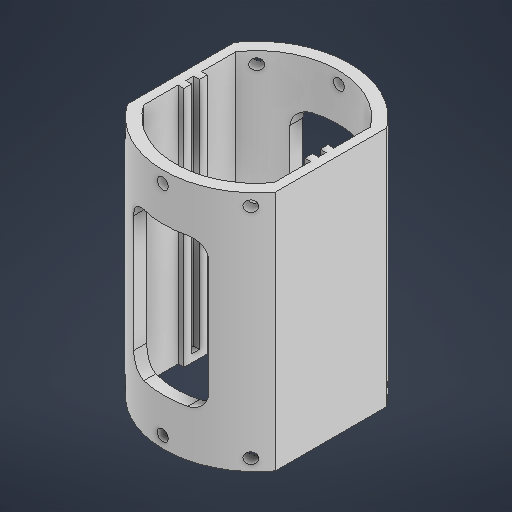
# Autodesk Inventor part: Avionics Holder
Saved by Autodesk Inventor 2027 (Build 310192060, 192F)
## iProperties
Created: 2026-07-27
Part Number: Avionics Holder
Material: PET Plastic
Document SubType Name: Modeling
Designer: troop
Density: 1.541 g/cm^3
Appearance: Default
Mass: 81.5144 g
Surface Area: 339.423 cm^2
Volume: 52.8971 cm^3
Author: troop
Autodesk Inventor part; units mm, degrees
sketch "Sketch1" plane through (0, 0, 0) normal (0, 1, 0) x (-1, 0, 0)
  line L0 (27.2914, 18.7675) -> (27.2914, -18.7675)
  line L1 (-26.6836, 19.6221) -> (-26.6836, -19.6221)
  arc A0 (27.2914, 18.7675) -> (-26.6836, 19.6221) centre (0, 0) ccw
  arc A1 (-26.6836, -19.6221) -> (27.2914, -18.7675) centre (0, 0) ccw
  line L2 (30.8982, 21.8545) -> (30.8982, -21.8545)
  line L3 (-30.3018, 22.6743) -> (-30.3018, -22.6743)
  arc A2 (30.8982, 21.8545) -> (-30.3018, 22.6743) centre (0, 0) ccw
  arc A3 (-30.3018, -22.6743) -> (30.8982, -21.8545) centre (0, 0) ccw
  line L4 (27.2914, -4.7625) -> (24.9102, -4.7625)
  line L5 (24.9102, -4.7625) -> (24.9102, -1.5875)
  line L6 (24.9102, -1.5875) -> (27.2914, -1.5875)
  line L7 (27.2914, -1.5875) -> (27.2914, -4.7625)
  line L8 (27.2914, 1.5875) -> (24.9102, 1.5875)
  line L9 (24.9102, 1.5875) -> (24.9102, 4.7625)
  line L10 (24.9102, 4.7625) -> (27.2914, 4.7625)
  line L11 (27.2914, 4.7625) -> (27.2914, 1.5875)
  line L12 (-26.6836, -4.7625) -> (-24.3023, -4.7625)
  line L13 (-24.3023, -4.7625) -> (-24.3023, -1.5875)
  line L14 (-24.3023, -1.5875) -> (-26.6836, -1.5875)
  line L15 (-26.6836, -1.5875) -> (-26.6836, -4.7625)
  line L16 (-26.6836, 1.5875) -> (-24.3023, 1.5875)
  line L17 (-24.3023, 1.5875) -> (-24.3023, 4.7625)
  line L18 (-24.3023, 4.7625) -> (-26.6836, 4.7625)
  line L19 (-26.6836, 4.7625) -> (-26.6836, 1.5875)
  point P0 (0.5069, 37.8426)
  point P1 (-25.4929, 1.5875)
  point P2 (27.2914, 4.7625)
  point P3 (27.2914, -1.5875)
  dimension "d5" = 61.2
  dimension "d6" = 43.709
  dimension "d7" = 30.8982
  dimension "d10" = 37.8426
  dimension "d11" = 21.8545
  dimension "d12" = 37.846
  dimension "d13" = 3.175
  dimension "d14" = 3.175
  dimension "d15" = 2.3813
  dimension "d16" = 2.3813
  dimension "d17" = 3.175
  dimension "d18" = 3.175
  dimension "d20" = 1.5875
  dimension "d21" = 1.5875
  dimension "d22" = 3.175
  dimension "d23" = 3.175
  dimension "d42" = 53.975
  dimension "d43" = 33.1216
  dimension "d44" = 33.1216
  dimension "d45" = 3.6068
  constraints: 40 end point, 10 parallel, 9 point on circle, 6 point on line, 4 centre point, 4 horizontal, 4 perpendicular, 2 vertical, 1 coincident, 1 midpoint
  measures "d5" distance between parallel lines of L3 L2
  measures "d6" distance of L2.start L2.end
  measures "d7" distance from line of L2 point (0, 0)
  measures "d10" vertical distance of point (0.507, 37.843) point (0, 0)
  measures "d11" vertical distance of A2.centre L2.start
  measures "d12" radius of A2
  measures "d13" distance between parallel lines of L8 L6
  measures "d14" distance from line of point (-25.493, 1.588) L14
  measures "d15" distance of L17.end L18.end
  measures "d16" distance of L9.end L10.end
  measures "d17" distance of L16.end L17.end
  measures "d18" distance of L12.end L13.end
  measures "d20" distance from line of A2.centre L14
  measures "d21" distance from line of point (0, 0) L6
  measures "d22" distance of L8.end L9.end
  measures "d23" distance of L4.end L5.end
  measures "d42" distance between parallel lines of L1 L0
  measures "d43" radius of A0
  measures "d44" radius of A1
  measures "d45" distance between parallel lines of L2 L0
extrude "Extrusion1" add sketch "Sketch1" along normal blind 98.425 contours L0 L8 L9 L10 | L18 L17 L16 L1 | L0 L4 L5 L6 | L14 L13 L12 L1 | L2 A3 L3 A2
ref_plane "Work Plane1" through (-0.5069, 98.425, 37.8426) normal (-0.0134, 0, 0.9999) x (0.9999, 0, 0.0134)
sketch "Sketch3" plane through (0, 0, 0) normal (0, -1, 0) x (1, 0, 0)
  line L0 (26.6836, 1.5875) -> (24.3023, 1.5875) projected
  line L1 (26.6836, 1.5875) -> (24.3023, 1.5875)
  line L2 (24.3023, 1.5875) -> (24.3023, -1.5875)
  line L3 (24.3023, -1.5875) -> (26.6836, -1.5875)
  line L4 (26.6836, -1.5875) -> (26.6836, 1.5875)
  line L5 (-27.2914, 1.5875) -> (-27.2914, -1.5875) projected
  line L6 (-27.2914, -1.5875) -> (-24.9102, -1.5875)
  line L7 (-24.9102, -1.5875) -> (-24.9102, 1.5875)
  line L8 (-24.9102, 1.5875) -> (-27.2914, 1.5875)
  line L9 (-27.2914, 1.5875) -> (-27.2914, -1.5875)
  point P0 (0, 0)
  point P1 (-28.7045, 1.5875)
  dimension "d32" = 2.3813
  constraints: 16 end point, 4 parallel, 2 horizontal, 2 perpendicular, 1 point on line
  measures "d32" distance of L5.end L6.end
extrude "Extrusion3" add sketch "Sketch3" against normal blind 3.175
ref_plane "Work Plane2" through (-0.5069, 98.425, 37.8426) normal (-0.0134, 0, 0.9999) x (0.9999, 0, 0.0134)
sketch "Sketch4" plane through (-0.5069, 98.425, 37.8426) normal (-0.0134, 0, 0.9999) x (0.9999, 0, 0.0134)
  circle A0 centre (0, -4.7625) radius 2.25
  line L0 (30.6027, 0) -> (-30.6027, 0) projected
  circle A1 centre (0, -93.6625) radius 2.25
  line L1 (30.6027, -98.425) -> (-30.6027, -98.425) projected
  point P0 (0, -98.425)
  point P1 (0, 0)
  point P2 (0, -98.425)
  dimension "d35" = 4.5
  dimension "d36" = 4.7625
  dimension "d37" = 0
  dimension "d46" = 4.5
  dimension "d47" = 0
  dimension "d48" = 4.7625
  constraints: 2 centre point, 2 midpoint
  measures "d35" diameter of A0
  measures "d36" distance from line of L0 A0.centre
  measures "d37" horizontal distance of point (0, 0) A0.centre
  measures "d46" diameter of A1
  measures "d47" horizontal distance of point (0, -98.425) A1.centre
  measures "d48" distance of point (0, -98.425) A1.centre
extrude "Extrusion4" cut sketch "Sketch4" against normal blind 76.2
ref_plane "Work Plane3" through (20.0422, 0, 32.1034) normal (0.5296, 0, 0.8483) x (0, 1, 0)
sketch "Sketch5" plane through (20.0422, 0, 32.1034) normal (0.5296, 0, 0.8483) x (0, 1, 0)
  circle A0 centre (4.7625, -6.8481) radius 2.25
  circle A1 centre (93.6625, -6.8481) radius 2.25
  line L0 (88.9, 0) -> (88.9, 34.7302) projected
  line L1 (0, -13.6963) -> (98.425, -13.6963) projected
  point P0 (0, 0)
  dimension "d49" = 4.5
  dimension "d52" = 4.5
  dimension "d54" = 4.7625
  dimension "d57" = 6.8481
  dimension "d60" = 6.8481
  dimension "d61" = 4.7625
  constraints: 2 centre point
  measures "d49" diameter of A0
  measures "d52" diameter of A1
  measures "d54" distance from line of L0 A1.centre
  measures "d57" distance from line of L1 A1.centre
  measures "d60" vertical distance of A0.centre point (0, 0)
  measures "d61" horizontal distance of point (0, 0) A0.centre
extrude "Extrusion5" cut sketch "Sketch5" against normal blind 25.4
ref_plane "Work Plane4" through (-21.4969, 0, 31.1481) normal (-0.568, 0, 0.823) x (0, -1, 0)
sketch "Sketch6" plane through (-21.4969, 0, 31.1481) normal (-0.568, 0, 0.823) x (0, -1, 0)
  circle A0 centre (-4.7625, -6.8481) radius 2.25
  circle A1 centre (-93.6625, -6.8481) radius 2.25
  line L0 (-98.425, 37.8182) -> (-98.425, -13.0164) projected
  point P0 (0, 0)
  dimension "d62" = 4.5
  dimension "d63" = 6.8481
  dimension "d64" = 4.7625
  dimension "d65" = 4.5
  dimension "d66" = 6.8481
  dimension "d67" = 4.7625
  constraints: 2 centre point
  measures "d62" diameter of A0
  measures "d63" vertical distance of point (0, 0) A0.centre
  measures "d64" horizontal distance of point (0, 0) A0.centre
  measures "d65" diameter of A1
  measures "d66" vertical distance of point (0, 0) A1.centre
  measures "d67" distance from line of L0 A1.centre
extrude "Extrusion6" cut sketch "Sketch6" against normal blind 25.4
ref_plane "Work Plane5" through (20.8949, 0, -31.5551) normal (0.5521, 0, -0.8338) x (0, 1, 0)
sketch "Sketch7" plane through (20.8949, 0, -31.5551) normal (0.5521, 0, -0.8338) x (0, 1, 0)
  circle A0 centre (4.7625, 6.8481) radius 2.25
  circle A1 centre (93.6625, 5.8982) radius 2.25
  line L0 (0, 12.7464) -> (98.425, 12.7464) projected
  line L1 (98.425, -37.8281) -> (98.425, 12.7464) projected
  point P0 (0, 0)
  dimension "d70" = 4.5
  dimension "d71" = 6.8481
  dimension "d72" = 4.7625
  dimension "d73" = 4.5
  dimension "d74" = 6.8481
  dimension "d75" = 4.7625
  constraints: 2 centre point
  measures "d70" diameter of A0
  measures "d71" vertical distance of point (0, 0) A0.centre
  measures "d72" horizontal distance of point (0, 0) A0.centre
  measures "d73" diameter of A1
  measures "d74" distance from line of L0 A1.centre
  measures "d75" distance from line of L1 A1.centre
extrude "Extrusion7" cut sketch "Sketch7" against normal blind 25.4
ref_plane "Work Plane6" through (-20.6549, 0, -31.7127) normal (-0.5458, 0, -0.8379) x (0, -1, 0)
sketch "Sketch8" plane through (-20.6549, 0, -31.7127) normal (-0.5458, 0, -0.8379) x (0, -1, 0)
  circle A0 centre (-4.7625, 6.8481) radius 2.25
  circle A1 centre (-93.6625, 6.8481) radius 2.25
  line L0 (-88.9, 0) -> (-9.525, 0) projected
  point P0 (0, 0)
  dimension "d78" = 4.5
  dimension "d79" = 4.5
  dimension "d80" = 6.8481
  dimension "d81" = 6.8481
  dimension "d82" = 4.7625
  dimension "d83" = 4.7625
  constraints: 2 centre point
  measures "d78" diameter of A0
  measures "d79" diameter of A1
  measures "d80" distance from line of L0 A1.centre
  measures "d81" vertical distance of point (0, 0) A0.centre
  measures "d82" horizontal distance of point (0, 0) A0.centre
  measures "d83" horizontal distance of L0.start A1.centre
extrude "Extrusion8" cut sketch "Sketch8" against normal blind 25.4
sketch "Sketch10" plane through (0, 0, 0) normal (0, 0, 1) x (1, 0, 0)
  line L0 (-15.6582, 79.375) -> (15.0618, 79.375)
  line L1 (15.0618, 79.375) -> (15.0618, 19.05)
  line L2 (15.0618, 19.05) -> (-15.6582, 19.05)
  line L3 (-15.6582, 19.05) -> (-15.6582, 79.375)
  line L4 (30.3018, 98.425) -> (-30.8982, 98.425) projected
  line L5 (30.3018, 0) -> (-30.8982, 0) projected
  line L6 (30.3018, 0) -> (30.3018, 98.425) projected
  line L7 (-30.8982, 0) -> (-30.8982, 98.425) projected
  point P0 (0, 0)
  dimension "d96" = 19.05
  dimension "d97" = 19.05
  dimension "d98" = 15.24
  dimension "d99" = 15.24
  constraints: 8 end point, 2 parallel, 1 horizontal, 1 perpendicular
  measures "d96" distance between parallel lines of L4 L0
  measures "d97" distance between parallel lines of L5 L2
  measures "d98" distance between parallel lines of L6 L1
  measures "d99" distance between parallel lines of L7 L3
extrude "Extrusion10" cut sketch "Sketch10" along normal mid plane 127 contours L0 L1 L2 L3
fillet "Fillet1" radius 6.35 8 edges at (-15.6582, 79.375, 31.8208) (15.0618, 79.375, 32.1093) (15.0618, 19.05, 32.1093) (15.0618, 19.05, -32.1093) (-15.6582, 19.05, 31.8208) (-15.6582, 19.05, -31.8208) (-15.6582, 79.375, -31.8208) (15.0618, 79.375, -32.1093)
body "Solid1"
